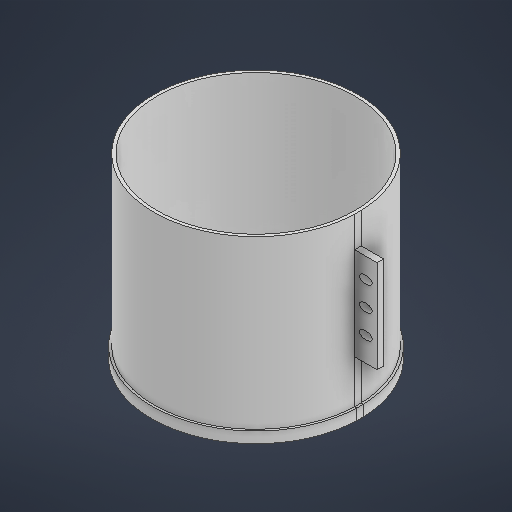
# Autodesk Inventor part: EDF Mockup
Saved by Autodesk Inventor 2026.3 (Build 303398000, 398)
## iProperties
Created: 2026-08-21
Part Number: EDF Mockup
Material: Generic
Document SubType Name: Modeling
Designer: joaqu
Density: 1 g/cm^3
Appearance: Default
Author: joaqu
Autodesk Inventor part; units mm, degrees
ref_plane "YZ Plane" through (0, 0, 0) normal (1, 0, 0) x (0, 1, 0)
sketch "Sketch4" plane through (0, 0, 0) normal (0, 1, 0) x (-1, 0, 0)
  line L0 (-56.7, 0) -> (-56.7, -1.5)
  line L1 (-56.7, 0) -> (-56.7, 1.5)
  line L2 (-46.4516, -1.5) -> (-56.7, -1.5)
  line L3 (-56.7, 1.5) -> (-46.4516, 1.5)
  arc A0 (-46.4516, -1.5) -> (0, -46.4758) centre (0, 0) ccw
  arc A1 (0, 46.4758) -> (-46.4516, 1.5) centre (0, 0) ccw
  line L4 (56.7, 0) -> (56.7, -1.5)
  line L5 (56.7, 0) -> (56.7, 1.5)
  line L6 (46.4516, -1.5) -> (56.7, -1.5)
  line L7 (56.7, 1.5) -> (46.4516, 1.5)
  arc A2 (0, -46.4758) -> (46.4516, -1.5) centre (0, 0) ccw
  arc A3 (46.4516, 1.5) -> (0, 46.4758) centre (0, 0) ccw
  point P0 (46.4516, 1.5)
  point P1 (-46.4516, 1.5)
  dimension "d19" = 1.5
  dimension "d20" = 1.5
  constraints: 16 end point, 10 point on circle, 4 centre point, 1 coincident, 1 horizontal, 1 perpendicular, 1 vertical
  measures "d19" distance of L0.start L0.end
  measures "d20" distance of L0.start L1.end
ref_plane "Work Plane1" through (0, 0, 0) normal (0, -1, 0) x (1, 0, 0)
ref_plane "Work Plane2" through (0, 0, 0) normal (0, -1, 0) x (1, 0, 0)
extrude "Extrusion4" add sketch "Sketch4" along normal blind 81
sketch "Sketch7" plane through (0, 81, 0) normal (0, 1, 0) x (1, 0, 0)
  point P0 (0, 0)
  point P1 (0, 0)
  constraints: 1 coincident
hole "Hole2" at (0, 81, 0) direction (0, -1, 0) diameter 90.2 end through all
sketch "Sketch8" plane through (0, 0, 0) normal (0, -1, 0) x (1, 0, 0)
  circle A0 centre (0, 0) radius 47.5
  circle A1 centre (0, 0) radius 46.5
  dimension "d30" = 95
  dimension "d31" = 93
  constraints: 2 centre point, 2 coincident
  measures "d30" diameter of A0
  measures "d31" diameter of A1
extrude "Extrusion5" add sketch "Sketch8" against normal blind 5 separate body
sketch "Sketch9" plane through (-56.7, 0, 1.5) normal (0, 0, 1) x (1, 0, 0)
  line L0 (10.2484, 81) -> (0, 81) projected
  ellipse E0 centre (5.1242, 35.7) end of major axis (5.1242, 37.45) minor radius 2.9
  point P0 (56.7, 0)
  constraints: 2 other
extrude "Extrusion6" cut sketch "Sketch9" against normal blind 5 bodies 1
pattern_linear "Rectangular Pattern1" count 3 spacing 11 along (0, 1, 0) of "Extrusion6" bodies 1
mirror "Mirror1" about plane through (0, 0, 0) normal (1, 0, 0) of "Extrusion6", "Rectangular Pattern1" bodies 1
sketch "Sketch10" plane through (-56.7, 0, 1.5) normal (0, 0, 1) x (1, 0, 0)
  ellipse E0 centre (5.1242, 35.7) end of major axis (2.2242, 35.7) minor radius 1.75 projected
  line L0 (5.1242, 24.7) -> (0, 24.7)
  line L1 (0, 0) -> (0, 81) projected
  line L2 (0, 0) -> (9.2, 0)
  line L3 (9.2, 0) -> (9.2, 5) projected
  line L4 (104.2, 5) -> (9.2, 5) projected
  line L5 (9.2, 5) -> (10.2242, 5)
  line L6 (10.2242, 5) -> (10.2242, 24.7)
  line L7 (10.2242, 24.7) -> (5.1242, 24.7)
  point P0 (56.7, 0)
  constraints: 10 end point, 3 point on line, 2 horizontal, 2 perpendicular, 1 parallel, 1 other
extrude "Extrusion7" cut sketch "Sketch10" against normal blind 5 contours L7 L6 L4 L3 L2 L1 L0 bodies 1
sketch "Sketch11" plane through (-56.7, 81, 1.5) normal (0, 0, 1) x (1, 0, 0)
  ellipse E0 centre (5.1242, -23.3) end of major axis (2.2242, -23.3) minor radius 1.75 projected
  line L0 (5.1242, -14.05) -> (0, -14.05)
  line L1 (0, -56.3) -> (0, 0) projected
  line L2 (0, 0) -> (10.2484, 0) projected
  line L3 (0, 0) -> (10.2484, 0)
  line L4 (10.2484, 0) -> (10.2484, -14.05)
  line L5 (10.2484, -14.05) -> (5.1242, -14.05)
  point P0 (56.7, -81)
  constraints: 8 end point, 2 collinear, 2 point on line, 1 horizontal, 1 perpendicular, 1 other
extrude "Extrusion8" cut sketch "Sketch11" against normal blind 5 contours L0 L1 L2 L4 L5 bodies 1
mirror "Mirror2" about plane through (0, 0, 0) normal (1, 0, 0) of "Extrusion8", "Extrusion7" bodies 1
body "Solid3"
body "Solid4"
